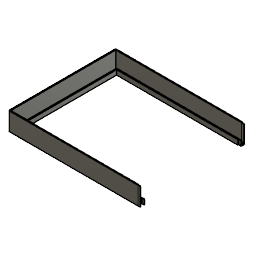
FrontFrame_Half (Autodesk Fusion 360 design; units mm, degrees)
part number: 2026-08-23-01-12-05-423
Autodesk Fusion 360 part; units mm, degrees
sketch "草图1" plane through (0, 0, 0) normal (0, 1, 0) x (1, 0, 0)
  line L0 (214.5, -89) -> (-214.5, -89)
  line L1 (-214.5, -89) -> (-214.5, 89)
  line L2 (-214.5, 89) -> (214.5, 89)
  line L3 (214.5, 89) -> (214.5, -89)
  line L4 (214.5, -89) -> (-214.5, 89) construction
  line L5 (-214.5, -89) -> (214.5, 89) construction
  dimension "d1" = 429
  dimension "d2" = 178
  constraint horizontal L0
  constraint perpendicular L0 L1
  constraint parallel L0 L2
  constraint parallel L1 L3
  constraint coincident L4 origin
  constraint coincident L5 origin
  measures "d1" distance of L1.end L2.end
  measures "d2" distance of L0.end L1.end
extrude "拉伸1" add sketch "草图1" along normal blind 2 makes body 1
sketch "草图2" plane through (0, 2, 0) normal (0, 1, 0) x (-1, 0, 0)
  line L0 (-214.5, -89) -> (214.5, -89)
  line L1 (214.5, -89) -> (214.5, 89)
  line L2 (214.5, 89) -> (-214.5, 89)
  line L3 (-214.5, 89) -> (-214.5, -89)
  line L4 (-212.5, 87.25) -> (212.5, 87.25)
  line L5 (212.5, 87.25) -> (212.5, -87.25)
  line L6 (212.5, -87.25) -> (-212.5, -87.25)
  line L7 (-212.5, -87.25) -> (-212.5, 87.25)
  line L8 (-212.5, 87.25) -> (212.5, -87.25) construction
  line L9 (212.5, 87.25) -> (-212.5, -87.25) construction
  line L10 (-205.5, 83.5) -> (205.5, 83.5)
  line L11 (207.5, 81.5) -> (207.5, -81.5)
  line L12 (205.5, -83.5) -> (-205.5, -83.5)
  line L13 (-207.5, -81.5) -> (-207.5, 81.5)
  line L14 (-207.5, 83.5) -> (207.5, -83.5) construction
  line L15 (207.5, 83.5) -> (-207.5, -83.5) construction
  line L16 (-204.5, 80.5) -> (204.5, 80.5)
  line L17 (204.5, 80.5) -> (204.5, -80.5)
  line L18 (204.5, -80.5) -> (-204.5, -80.5)
  line L19 (-204.5, -80.5) -> (-204.5, 80.5)
  line L20 (-204.5, 80.5) -> (204.5, -80.5) construction
  line L21 (204.5, 80.5) -> (-204.5, -80.5) construction
  arc A0 (-207.5, -81.5) -> (-205.5, -83.5) centre (-205.5, -81.5) ccw
  arc A1 (-205.5, 83.5) -> (-207.5, 81.5) centre (-205.5, 81.5) ccw
  arc A2 (207.5, 81.5) -> (205.5, 83.5) centre (205.5, 81.5) ccw
  arc A3 (205.5, -83.5) -> (207.5, -81.5) centre (205.5, -81.5) ccw
  dimension "d5" = 425
  dimension "d6" = 174.5
  dimension "d7" = 415
  dimension "d8" = 167
  dimension "d9" = 409
  dimension "d10" = 161
  dimension "d11" = 2
  dimension "d12" = 2
  dimension "d13" = 2
  dimension "d14" = 2
  constraint horizontal L4
  constraint perpendicular L4 L5
  constraint parallel L4 L6
  constraint parallel L5 L7
  constraint coincident L8 origin
  constraint coincident L9 origin
  constraint horizontal L10
  constraint perpendicular L10 L11
  constraint parallel L10 L12
  constraint parallel L11 L13
  constraint coincident L14 origin
  constraint coincident L15 origin
  constraint horizontal L16
  constraint perpendicular L16 L17
  constraint parallel L16 L18
  constraint parallel L17 L19
  constraint coincident L20 origin
  constraint coincident L21 origin
  constraint coincident L15.end L12
  constraint coincident L15.end L13
  constraint tangent L12 A0
  constraint tangent L13 A0
  constraint coincident L14.start L13
  constraint coincident L14.start L10
  constraint tangent L13 A1
  constraint tangent L10 A1
  constraint coincident L15.start L10
  constraint coincident L15.start L11
  constraint tangent L10 A2
  constraint tangent L11 A2
  constraint coincident L14.end L12
  constraint coincident L14.end L11
  constraint tangent L12 A3
  constraint tangent L11 A3
  measures "d5" distance of L5.end L6.end
  measures "d6" distance of L4.end L5.end
  measures "d7" distance of L14.end L15.end
  measures "d8" distance of L15.start L14.end
  measures "d9" distance of L17.end L18.end
  measures "d10" distance of L16.end L17.end
  measures "d11" radius of A0
  measures "d12" radius of A1
  measures "d13" radius of A2
  measures "d14" radius of A3
extrude "拉伸2" add sketch "草图2" along normal blind 43 contours L10 L11 L12 L13 A0 A1 A2 A3 bodies 1
extrude "拉伸3" add sketch "草图2" along normal blind 28 contours L0 L1 L2 L3 bodies 1
extrude "拉伸4" cut sketch "草图2" against normal blind 2 contours L16 L17 L18 L19 bodies 1
split "分割1" by plane through (0, 0, 0) normal (1, 0, 0) bodies 1 makes body 2 at (136.3333, 30, 80.5)
delete_body "移除实体1" bodies 2
fillet "圆角1" radius 1 1 edges at (-214.5, 15, 89) on bodies 1
fillet "圆角2" radius 1 1 edges at (-214.5, 15, -89) on bodies 1
sketch "草图3" plane through (0, 0, 0) normal (1, 0, 0) x (0, 0, -1)
  line L0 (-83.5, 45) -> (-83.5, 2)
  line L1 (-83.5, 2) -> (-87.25, 2)
  line L2 (-87.25, 2) -> (-87.25, 30)
  line L3 (-87.25, 30) -> (-89, 30)
  line L4 (-89, 30) -> (-89, 0)
  line L5 (-89, 0) -> (-80.5, 0)
  line L6 (-80.5, 0) -> (-80.5, 45)
  line L7 (-80.5, 45) -> (-83.5, 45)
  line L8 (-88.125, 30) -> (-88.125, 0)
  line L9 (-82, 45) -> (-82, 0)
  constraint midpoint L3 L8.start
  constraint coincident L5 L8.end
  constraint perpendicular L5 L8
  constraint midpoint L7 L9.start
  constraint coincident L5 L9.end
  constraint perpendicular L5 L9
extrude "拉伸5" add sketch "草图3" along normal blind 4 contours L5 L6 L7 L9 | L3 L4 L5 L8 bodies 1
sketch "草图4" plane through (0, 0, 0) normal (1, 0, 0) x (0, 0, -1)
  line L0 (83.5, 2) -> (83.5, 45)
  line L1 (83.5, 45) -> (80.5, 45)
  line L2 (80.5, 45) -> (80.5, 0)
  line L3 (80.5, 0) -> (89, 0)
  line L4 (89, 0) -> (89, 30)
  line L5 (89, 30) -> (87.25, 30)
  line L6 (87.25, 30) -> (87.25, 2)
  line L7 (87.25, 2) -> (83.5, 2)
  line L8 (82, 45) -> (82, 0)
  line L9 (88.125, 30) -> (88.125, 0)
  constraint midpoint L1 L8.start
  constraint coincident L3 L8.end
  constraint perpendicular L3 L8
  constraint midpoint L5 L9.start
  constraint coincident L3 L9.end
  constraint perpendicular L3 L9
extrude "拉伸6" cut sketch "草图4" against normal blind 4.2 contours L1 L2 L3 L8 | L3 L4 L5 L9 bodies 1
extrude "拉伸7" cut 1 faces at (-2.8, 20, -88.125) along direction (0, 0, 1) blind 0.1 on bodies 1 bodies 1
extrude "拉伸8" cut 1 faces at (-1.4, 30, -82) along direction (0, 0, -1) blind 0.1 on bodies 1 bodies 1
extrude "拉伸9" cut 1 faces at (1.3333, 20, 88.125) along direction (0, 0, 1) blind 0.1 on bodies 1 bodies 1
extrude "拉伸10" cut 1 faces at (1.3333, 30, 82) along direction (0, 0, -1) blind 0.1 on bodies 1 bodies 1
extrude "拉伸11" cut 1 faces at (-136.6667, 45, 82.5) along direction (0, -1, 0) blind 37 on bodies 1 bodies 1
extrude "拉伸12" cut 1 faces at (-65.5, 5.3333, 80.5) along direction (0, 0, 1) blind 1 on bodies 1 bodies 1
extrude "拉伸13" cut 1 faces at (-137.7333, 5.3333, -80.5) along direction (0, 0, -1) blind 1 on bodies 1 bodies 1
extrude "拉伸14" add 1 faces at (1.3333, 5.3333, 81.9) along direction (0, 0, 1) blind 0.5 on bodies 1 bodies 1
extrude "拉伸15" cut 1 faces at (-1.4, 5.3333, -82.1) along direction (0, 0, -1) blind 0.5 on bodies 1 bodies 1
extrude "拉伸16" cut 1 faces at (-204.5, 5.3333, 27.1667) along direction (-1, 0, 0) blind 1 on bodies 1 bodies 1
extrude "拉伸17" add 1 faces at (-1.4, 5.3333, -82.6) along direction (0, 0, 1) blind 0.1 on bodies 1 bodies 1
extrude "拉伸18" add 1 faces at (1.3333, 20, 88.225) along direction (0, 0, -1) blind 0.1 on bodies 1 bodies 1
move_face "偏移面1" offset 0.5 1 faces at (0, 0.6667, -84.675) on bodies 1
extrude "拉伸19" add 2 faces at (-4.2, 10, -88.675) (-4.2, 5.3333, -81.8333) along direction (1, 0, 0) blind 0.5 on bodies 1 bodies 1
extrude "拉伸20" add 2 faces at (4, 10, 88.4167) (4, 5.3333, 81.8) along direction (1, 0, 0) blind 0.5 on bodies 1 bodies 1
extrude "拉伸21" add 1 faces at (0, 0.6667, 84.675) along direction (1, 0, 0) blind 0.5 on bodies 1 bodies 1
